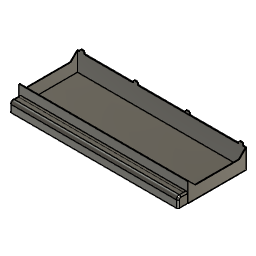
Large_Drawer_PRINT (Autodesk Fusion 360 design; units mm, degrees)
Autodesk Fusion 360 part; units mm, degrees
sketch "Sketch1" plane through (0, 0, 0) normal (0, 0, 1) x (1, 0, 0)
  line L0 (0, 0) -> (229.4, 0)
  line L1 (229.4, 0) -> (229.4, 80)
  line L2 (229.4, 80) -> (0, 80)
  line L3 (0, 80) -> (0, 0)
  dimension "d1" = 229.4
  dimension "d2" = 80
  constraint horizontal L0
  constraint vertical L1
  constraint horizontal L2
  constraint vertical L3
  constraint coincident L0.start L3.end
  measures "d1" distance of L0.start L0.end
  measures "d2" distance of L0.end L1.end
extrude "Extrude1" add sketch "Sketch1" along normal blind 26.2 makes body 1
shell "Shell1" thickness 0.8 removed faces 1 at (76.4667, 26.6667, 26.2) on bodies 1
ref_plane "WorkPlane1" through (211, 40, 13.1) normal (1, 0, 0) x (0, 1, 0)
sketch "Sketch3" plane through (0, 80, 0) normal (0, 1, 0) x (-1, 0, 0)
  line L0 (-229.4, 0) -> (0, 0)
  line L1 (0, 0) -> (0, 26.2)
  line L2 (0, 26.2) -> (-229.4, 26.2)
  line L3 (-229.4, 26.2) -> (-229.4, 0)
  line L4 (-114.7, 26.2) -> (-114.7, 0) construction
  line L5 (-225.15, 27.45) -> (-225.15, 28.45)
  line L6 (-223.9, 29.7) -> (-220.9, 29.7)
  line L7 (-219.65, 28.45) -> (-219.65, 27.45)
  line L8 (-226.4, 26.2) -> (-218.4, 26.2)
  arc A0 (-226.4, 26.2) -> (-225.15, 27.45) centre (-226.4, 27.45) ccw
  arc A1 (-223.9, 29.7) -> (-225.15, 28.45) centre (-223.9, 28.45) ccw
  arc A2 (-219.65, 28.45) -> (-220.9, 29.7) centre (-220.9, 28.45) ccw
  arc A3 (-219.65, 27.45) -> (-218.4, 26.2) centre (-218.4, 27.45) ccw
  arc A4 (-4.25, 28.45) -> (-5.5, 29.7) centre (-5.5, 28.45) ccw
  line L9 (-5.5, 29.7) -> (-8.5, 29.7)
  arc A5 (-11, 26.2) -> (-9.75, 27.45) centre (-11, 27.45) ccw
  arc A6 (-4.25, 27.45) -> (-3, 26.2) centre (-3, 27.45) ccw
  line L10 (-4.25, 27.45) -> (-4.25, 28.45)
  line L11 (-3, 26.2) -> (-11, 26.2)
  arc A7 (-8.5, 29.7) -> (-9.75, 28.45) centre (-8.5, 28.45) ccw
  line L12 (-9.75, 28.45) -> (-9.75, 27.45)
  line L13 (-151.4, 29.7129) -> (-148.4, 29.7129)
  arc A8 (-151.4, 29.7129) -> (-152.65, 28.4629) centre (-151.4, 28.4629) ccw
  line L14 (-152.65, 27.4629) -> (-152.65, 28.4629)
  arc A9 (-153.9, 26.2129) -> (-152.65, 27.4629) centre (-153.9, 27.4629) ccw
  arc A10 (-147.15, 27.4629) -> (-145.9, 26.2129) centre (-145.9, 27.4629) ccw
  line L15 (-153.9, 26.2129) -> (-145.9, 26.2129)
  line L16 (-147.15, 28.4629) -> (-147.15, 27.4629)
  arc A11 (-147.15, 28.4629) -> (-148.4, 29.7129) centre (-148.4, 28.4629) ccw
  line L17 (-81, 29.7) -> (-78, 29.7)
  arc A12 (-81, 29.7) -> (-82.25, 28.45) centre (-81, 28.45) ccw
  line L18 (-82.25, 27.45) -> (-82.25, 28.45)
  arc A13 (-83.5, 26.2) -> (-82.25, 27.45) centre (-83.5, 27.45) ccw
  arc A14 (-76.75, 28.45) -> (-78, 29.7) centre (-78, 28.45) ccw
  line L19 (-76.75, 28.45) -> (-76.75, 27.45)
  arc A15 (-76.75, 27.45) -> (-75.5, 26.2) centre (-75.5, 27.45) ccw
  point P0 (-222.4, 29.7)
  point P1 (-7, 29.7)
  dimension "d18" = 7
  dimension "d19" = 3.5
  dimension "d20" = 5.5
  dimension "d21" = 1.25
  dimension "d62" = 3.5
  dimension "d63" = 5.5
  dimension "d64" = 1.25
  dimension "d65" = 114.3
  dimension "d66" = 67
  dimension "d75" = 5.5
  dimension "d76" = 1.25
  dimension "d77" = 3.5
  dimension "d78" = 67
  dimension "d79" = 54.15
  constraint midpoint L2 L4.start
  constraint perpendicular L2 L4
  constraint coincident L0 L4.end
  constraint horizontal L6
  constraint tangent L6 A1
  constraint tangent L5 A1
  constraint tangent L5 A0
  constraint tangent L6 A2
  constraint tangent L7 A2
  constraint tangent L7 A3
  constraint tangent L8 A3
  constraint tangent L8 A0
  constraint equal A0 A1
  constraint equal A1 A2
  constraint equal A2 A3
  constraint collinear L2 L8
  constraint vertical L7
  constraint vertical L5
  constraint midpoint L6 P0
  constraint symmetric L4 L5.start A6.start
  constraint symmetric L4 L5.end A4.start
  constraint symmetric L4 L6.start A4.end
  constraint symmetric L4 L6.end L9.end
  constraint symmetric L4 L7.start A7.end
  constraint symmetric L4 L7.end A5.end
  constraint symmetric L4 L8.start A6.end
  constraint symmetric L4 L8.end A5.start
  constraint symmetric L4 P0 P1
  constraint symmetric L4 A0 A6
  constraint symmetric L4 A1 A4
  constraint symmetric L4 A2 A7
  constraint symmetric L4 A3 A5
  constraint horizontal L13
  constraint tangent L13 A8
  constraint tangent A8 L14
  constraint tangent L14 A9
  constraint tangent L13 A11
  constraint tangent L16 A11
  constraint tangent A10 L16
  constraint tangent A10 L15
  constraint tangent A9 L15
  constraint equal A8 A9
  constraint equal A8 A11
  constraint equal A10 A11
  constraint vertical L16
  constraint vertical L14
  constraint horizontal L17
  constraint tangent L17 A12
  constraint tangent A12 L18
  constraint tangent L18 A13
  constraint tangent L17 A14
  constraint tangent A14 L19
  constraint tangent L19 A15
  constraint equal A12 A13
  constraint equal A12 A14
  constraint equal A14 A15
  constraint vertical L19
  constraint vertical L18
  measures "d18" distance of L3 P0
  measures "d19" distance of L6 L8
  measures "d20" distance of L5 L7
  measures "d21" radius of A0
  measures "d62" distance of L13 L15
  measures "d63" distance of L14 L16
  measures "d64" radius of A9
  measures "d66" distance of L7 L14
  measures "d75" distance of L18 L19
  measures "d76" radius of A13
  measures "d77" distance of L2 L17
  measures "d78" distance of L12 L19
extrude "Extrude3" add sketch "Sketch3" against normal blind 0.8 contours L2 L5 L6 L7 L8 A0 A1 A2 A3 | L2 A4 L9 A5 A6 L10 L11 A7 L12 | L2 L17 A12 L18 A13 A14 L19 A15 | L13 A8 L14 A9 A10 L15 L16 A11 bodies 1 makes body 2 at (150.4, 80, 28.2129)
sketch "Sketch4" plane through (229.4, 0, 0) normal (1, 0, 0) x (0, 1, 0)
  line L0 (0, 0) -> (80, 0)
  line L1 (80, 0) -> (80, 26.2)
  line L2 (80, 26.2) -> (0, 26.2)
  line L3 (0, 26.2) -> (0, 0)
  line L4 (0.9071, 26.2) -> (10.1071, 17)
  line L5 (0.9071, 26.2) -> (7.8528, 26.2) construction
  line L6 (10.1071, 17) -> (69.7311, 17)
  line L7 (69.7311, 17) -> (78.9311, 26.2)
  line L8 (78.9311, 26.2) -> (0.9071, 26.2)
  dimension "d24" = 45
  dimension "d25" = 135
  dimension "d26" = 17
  constraint horizontal L5
  constraint coincident L2 L4.start
  constraint horizontal L6
  constraint coincident L2 L7.end
  measures "d24" angle of L4 L5
  measures "d25" angle of L6 L7
  measures "d26" distance of L0 L6
extrude "Extrude4" cut sketch "Sketch4" against normal up to surface (229.4 mm away) contours L2 L4 L6 L7 L8 bodies 1
extrude "Extrude5" add 1 faces at (104.3, 79.2, 9.2667) along direction (0, -1, 0) blind 0.4 on bodies 1 bodies 1
sketch "Sketch5" plane through (0, 0, 0) normal (0, -1, 0) x (1, 0, 0)
  line L0 (0, 0) -> (229.4, 0)
  line L1 (229.4, 0) -> (229.4, 26.2)
  line L2 (229.4, 26.2) -> (0, 26.2)
  line L3 (0, 26.2) -> (0, 0)
  line L4 (0.5, 13.8) -> (228.9, 13.8)
  line L5 (228.9, 13.8) -> (228.9, 13)
  line L6 (228.9, 13) -> (0.5, 13)
  line L7 (0.5, 13) -> (0.5, 13.8)
  dimension "d31" = 0.5
  dimension "d32" = 0.5
  dimension "d33" = 0.8
  dimension "d34" = 13
  constraint horizontal L4
  constraint vertical L5
  constraint horizontal L6
  constraint vertical L7
  measures "d31" distance of L3 L7
  measures "d32" distance of L1 L5
  measures "d33" distance of L4 L6
  measures "d34" distance of L0 L6
extrude "Extrude6" add sketch "Sketch5" along normal blind 13 contours L4 L5 L6 L7 bodies 1
sketch "Sketch6" plane through (0, 0, 13) normal (0, 0, -1) x (1, 0, 0)
  line L0 (0.5, 0) -> (228.9, 0)
  line L1 (228.9, 0) -> (228.9, 13)
  line L2 (228.9, 13) -> (0.5, 13)
  line L3 (0.5, 13) -> (0.5, 0)
  line L4 (0.5, 13) -> (31.3, 13)
  line L5 (31.3, 12.2) -> (0.5, 12.2)
  line L6 (0.5, 12.2) -> (0.5, 13)
  line L7 (31.3, 13) -> (228.9, 13)
  line L8 (31.3, 12.2) -> (228.9, 12.2)
  line L9 (228.9, 12.2) -> (228.9, 13)
  dimension "d37" = 0.8
  constraint horizontal L4
  constraint horizontal L5
  constraint vertical L6
  constraint coincident L2.end L3.start
  constraint coincident L1.end L2.start
  constraint coincident L1 L8.end
  constraint perpendicular L1 L8
  measures "d37" distance of L2.end L5.end
extrude "Extrude7" add sketch "Sketch6" along normal blind 13 contours L1 L2 L3 L4 L5 L6 L7 L8 L9 bodies 1
sketch "Sketch8" plane through (0, 0, 13) normal (0, 0, -1) x (1, 0, 0)
  line L0 (228.9, 12.2) -> (0.5, 12.2)
  line L1 (0.5, 12.2) -> (0.5, 0)
  line L2 (0.5, 0) -> (228.9, 0)
  line L3 (228.9, 0) -> (228.9, 12.2)
  line L4 (1.3, 0) -> (0.5, 0)
  line L5 (0.5, 0) -> (0.5, 12.2)
  line L6 (0.5, 12.2) -> (1.3, 12.2)
  line L7 (1.3, 12.2) -> (1.3, 0)
  line L8 (228.9, 0) -> (228.1, 0)
  line L9 (228.1, 0) -> (228.1, 12.2)
  line L10 (228.1, 12.2) -> (228.9, 12.2)
  line L11 (228.9, 12.2) -> (228.9, 0)
  dimension "d45" = 0.8
  dimension "d46" = 0.8
  constraint horizontal L4
  constraint vertical L5
  constraint horizontal L6
  constraint vertical L7
  constraint coincident L0.end L1.start
  constraint coincident L2 L4.start
  constraint horizontal L8
  constraint vertical L9
  constraint horizontal L10
  constraint vertical L11
  constraint coincident L0 L9.end
  constraint coincident L2.end L3.start
  measures "d45" distance of L9.end L0.start
  measures "d46" distance of L0.end L6.end
extrude "Extrude9" add sketch "Sketch8" along normal blind 13 contours L0 L2 L3 L8 L9 L10 L11 | L0 L1 L2 L4 L5 L6 L7 bodies 1
fillet "Fillet2" radius 4 2 edges at (114.7, -12.2, 13) (114.7, -13, 13.8) on bodies 1
chamfer "Chamfer1" distance 3 angle 45 1 edges at (114.7, 0, 13) on bodies 1
fillet "Fillet4" radius 2 6 edges at (1.3, -12.2, 4.5) (1.3, -11.0284, 11.8284) (1.3, -5.6, 13) (0.5, -4.5, 13.8) (0.5, -11.8284, 12.6284) (0.5, -13, 4.9) on bodies 1
fillet "Fillet5" radius 2 3 edges at (228.1, -5.6, 13) (228.1, -11.0284, 11.8284) (228.1, -12.2, 4.5) on bodies 1
fillet "Fillet6" radius 2 3 edges at (228.9, -4.5, 13.8) (228.9, -11.8284, 12.6284) (228.9, -13, 4.9) on bodies 1
equation "d1 = 230.2 mm - 0.8 mm"
